Xshape_calibration_v5 (Autodesk Fusion 360 design; units mm, degrees)
part number: 2026-11-16-08-53-42-232
Autodesk Fusion 360 part; units mm, degrees
sketch "Sketch1" plane through (0, 0, 0) normal (0, 1, 0) x (1, 0, 0)
  circle A0 centre (134.4733, -2.4753) radius 1.9
  circle A1 centre (149.4493, 14.7502) radius 2.75
  circle A2 centre (141.8612, 5.6744) radius 1.9
  circle A3 centre (130.4074, 8.6341) radius 2.75
  circle A4 centre (126.1832, -10.9148) radius 2.75
  circle A5 centre (164.267, 1.3175) radius 2.75
  circle A6 centre (160.0428, -18.2313) radius 2.75
  circle A7 centre (141.0009, -24.3474) radius 2.75
  circle A8 centre (141.8612, 5.6744) radius 2.15
  circle A9 centre (152.6131, 3.3511) radius 2.15
  circle A10 centre (148.589, -15.2716) radius 2.15
  circle A11 centre (155.977, -7.1219) radius 2.15
  circle A12 centre (137.8371, -12.9483) radius 2.15
  circle A13 centre (134.4733, -2.4753) radius 2.15
  circle A14 centre (155.977, -7.1219) radius 1.9
  arc A15 (176.1681, 5.1401) -> (114.2821, -14.7373) centre (145.2251, -4.7986) ccw
  line L0 (145.2251, -4.7986) -> (-84.7749, -4.7986)
  line L1 (-84.7749, -4.7986) -> (-84.7749, 15.2014)
  circle A16 centre (-90.2749, -14.3249) radius 1.9
  circle A17 centre (-79.2749, -14.3249) radius 1.9
  circle A18 centre (-79.2749, 4.7277) radius 1.9
  circle A19 centre (126.1832, -10.9148) radius 2.4
  line L2 (145.2251, -37.2986) -> (-84.7749, -37.2986)
  circle A20 centre (160.0428, -18.2313) radius 2.4
  circle A21 centre (-84.7749, 15.2014) radius 2.4
  circle A22 centre (-90.2749, 4.7277) radius 1.9
  circle A23 centre (130.4074, 8.6341) radius 2.4
  line L3 (-84.7749, -4.7986) -> (-90.2749, 4.7277)
  circle A24 centre (-102.0954, 5.2014) radius 2.4
  circle A25 centre (164.267, 1.3175) radius 2.4
  line L4 (-84.7749, 27.7014) -> (145.2251, 27.7014)
  circle A26 centre (-84.7749, -4.7986) radius 32.5
  circle A27 centre (-102.0954, -14.7986) radius 2.4
  circle A28 centre (152.6131, 3.3511) radius 1.9
  circle A29 centre (-95.7749, -4.7986) radius 1.9
  circle A30 centre (145.2251, -4.7986) radius 32.5
  circle A31 centre (149.4493, 14.7502) radius 2.4
  circle A32 centre (148.589, -15.2716) radius 1.9
  circle A33 centre (141.0009, -24.3474) radius 2.4
  circle A34 centre (-67.4544, -14.7986) radius 2.4
  circle A35 centre (137.8371, -12.9483) radius 1.9
  circle A36 centre (-67.4544, 5.2014) radius 2.4
  circle A37 centre (-73.7749, -4.7986) radius 1.9
  circle A38 centre (-84.7749, -24.7986) radius 2.4
  line L5 (30.2251, -4.7986) -> (30.2251, -8.7986)
  line L6 (32.2251, -4.7986) -> (28.2251, -4.7986)
  line L7 (28.2251, -4.7986) -> (28.2251, -12.7986)
  line L8 (28.2251, -12.7986) -> (32.2251, -12.7986)
  line L9 (32.2251, -12.7986) -> (32.2251, -4.7986)
  line L10 (32.2251, -4.7986) -> (28.2251, -12.7986) construction
  line L11 (28.2251, -4.7986) -> (32.2251, -12.7986) construction
  line L12 (30.2251, -4.7986) -> (30.2251, 3.2014)
  line L13 (28.2251, -4.7986) -> (24.2251, -4.7986)
  line L14 (32.2251, -4.7986) -> (36.2251, -4.7986)
  line L15 (24.2251, -4.7986) -> (30.2251, 3.2014)
  line L16 (36.2251, -4.7986) -> (30.2251, 3.2014)
  point P0 (30.2251, -8.7986)
  dimension "d2" = 360
  dimension "d4" = 360
  dimension "d6" = 360
  dimension "d7" = 65
  dimension "d8" = 4.8
  dimension "d9" = 65
  dimension "d10" = 230
  dimension "d11" = 20
  dimension "d12" = 3.8
  dimension "d13" = 30
  dimension "d14" = 11
  dimension "d15" = 3.8
  dimension "d16" = 4.8
  dimension "d17" = 4
  dimension "d18" = 4
  dimension "d19" = 8
  dimension "d20" = 4
  dimension "d21" = 4
  constraint concentric A15 A30
  constraint coincident A15.centre L0.start
  constraint horizontal L0
  constraint coincident L0.end L1.start
  constraint perpendicular L0 L1
  constraint coincident L1.end A21.centre
  constraint coincident A22.centre L3.end
  constraint concentric A1 A31
  constraint concentric A2 A8
  constraint coincident L4.start A26
  constraint coincident L4.end A15
  constraint coincident L4.end A30
  constraint coincident L2.start A30
  constraint coincident L2.end A26
  constraint tangent L2 A26
  constraint tangent L4 A26
  constraint tangent L2 A30
  constraint tangent L4 A30
  constraint midpoint L0 L5.start
  constraint perpendicular L0 L5
  constraint horizontal L6
  constraint perpendicular L6 L7
  constraint parallel L6 L8
  constraint parallel L7 L9
  constraint coincident L10 P0
  constraint coincident L11 P0
  constraint coincident P0 L5.end
  constraint perpendicular L6 L12
  constraint perpendicular L7 L13
  constraint perpendicular L9 L14
  measures "d7" diameter of A30
  measures "d8" diameter of A21
  measures "d9" diameter of A26
  measures "d10" distance of A15.centre L0.end
  measures "d11" distance of L0.end L1.end
  measures "d12" diameter of A22
  measures "d13" angle of L1 L3
  measures "d14" distance of L0.end A22.centre
  measures "d15" diameter of A2
  measures "d16" diameter of A31
  measures "d17" distance of L5.start P0
  measures "d18" distance of L7.end L8.end
  measures "d19" distance of L5.start L12.end
  measures "d20" distance of L6.end L13.end
  measures "d21" distance of L6.start L14.end
extrude "Extrude1" add sketch "Sketch1" along normal blind 12 contours A1 | A3 | A4 | A5 | A6 | A7 | A8 | A9 | A10 | A11 | A12 | A13 | A15 A30 | A15 L0 L4 A26 A30 L15 L16 | A15 L0 L2 A26 A30 L7 L8 L9 L13 L14 | A26
